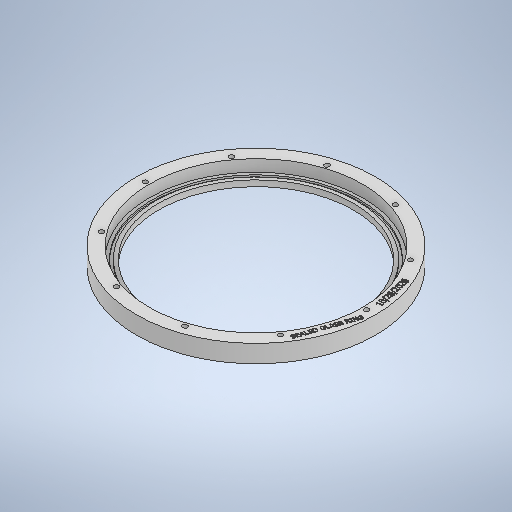
# Autodesk Inventor part: SealedGlassRing_Lowered
Saved by Autodesk Inventor 2025 (Build 290162000, 162)
## iProperties
Created: 2026-10-28
Part Number: SealedGlassRing_Lowered
Material: Generic
Document SubType Name: Modeling
Designer: madhami
Density: 1 g/cm^3
Appearance: Default
Author: madhami
Autodesk Inventor part; units mm, degrees
ref_plane "YZ Plane" through (0, 0, 0) normal (1, 0, 0) x (0, 1, 0)
ref_plane "XZ Plane" through (0, 0, 0) normal (0, 1, 0) x (-1, 0, 0)
ref_plane "XY Plane" through (0, 0, 0) normal (0, 0, 1) x (1, 0, 0)
sketch "Sketch1" plane through (0, 0, 0) normal (1, 0, 0) x (0, 1, 0)
  line L0 (33.6846, 0) -> (-3.2071, 0)
  line L1 (6.7, -110) -> (0, -110)
  line L2 (0, -114) -> (2.5, -114)
  line L3 (2.5, -114) -> (2.5, -117)
  line L4 (2.5, -117) -> (0, -117)
  line L5 (0, -117) -> (0, -135)
  line L6 (0, -135) -> (20, -135)
  line L7 (20, -135) -> (20, -120.5)
  line L8 (20, -120.5) -> (6.7, -120.5)
  line L9 (6.7, -120.5) -> (6.7, -117)
  line L10 (6.7, -117) -> (4.7, -117)
  line L11 (4.7, -117) -> (4.7, -114)
  line L12 (4.7, -114) -> (6.7, -114)
  line L13 (6.7, -114) -> (6.7, -110)
  line L14 (0, -114) -> (0, -110)
  point P0 (0, 0)
  dimension "d0" = 270
  dimension "d1" = 220
  dimension "d2" = 241
  dimension "d4" = 20
  dimension "d5" = 3
  dimension "d6" = 228
  dimension "d7" = 13.3
  dimension "d8" = 2
  dimension "d9" = 2.5
  constraints: 30 end point, 7 perpendicular, 4 point on line, 2 horizontal, 1 parallel, 1 vertical
  measures "d0" diameter of L6 L0
  measures "d1" diameter of L1 L0
  measures "d2" diameter of L8 L0
  measures "d4" distance between parallel lines of L5 L7
  measures "d5" distance of L10.end L11.end
  measures "d6" diameter of L12 L0
  measures "d7" distance between parallel lines of L7 L9
  measures "d8" distance between parallel lines of L9 L11
  measures "d9" distance between parallel lines of L5 L3
revolve "Revolution1" add sketch "Sketch1" angle 360 about axis through (0, 33.6846, 0) along (0, -1, 0)
sketch "Sketch2" plane through (0, 20, 0) normal (0, 1, 0) x (1, 0, 0)
  circle A0 centre (0, 0) radius 125
  line L0 (-189, 0) -> (189, 0) projected
  point P0 (-125, 0)
  dimension "d18" = 250
  constraints: 1 coincident, 1 horizontal alignment, 1 point on line, 2 other
hole "Hole1" at (-125, 20, 0) direction (0, -1, 0) diameter 5.5 end through all
pattern_circular "Circular Pattern1" count 10 over 360 about axis through (0, -10, 0) along (0, 1, 0) of "Hole1"
sketch "Sketch3" plane through (0, 20, 0) normal (0, 1, 0) x (1, 0, 0)
  line L0 (106.4888, -68.4672) -> (128.0893, -6.4393) construction
  line L1 (128.0893, -6.4393) -> (133.5161, -8.3291) construction
  line L2 (133.5161, -8.3291) -> (111.9157, -70.357) construction
  line L3 (111.9157, -70.357) -> (106.4888, -68.4672) construction
  line L4 (123.8949, 10.0524) -> (114.5166, 51.3311) construction
  line L5 (114.5166, 51.3311) -> (121.899, 53.0083) construction
  line L6 (121.899, 53.0083) -> (131.2773, 11.7297) construction
  line L7 (131.2773, 11.7297) -> (123.8949, 10.0524) construction
  spline S0 degree 2 poles (112.004, -68.3756) (111.8255, -68.8883) (111.3607, -69.5331) (111.097, -69.7974) knots 0 0 0 1 2 2 2
  line L8 (111.097, -69.7974) -> (110.3088, -69.5229)
  line L9 (110.3088, -69.5229) -> (110.3248, -69.4769)
  spline S1 degree 2 poles (110.3248, -69.4769) (110.7235, -69.2683) (111.3181, -68.5958) (111.4447, -68.2323) knots 0 0 0 1 2 2 2
  spline S2 degree 2 poles (111.4447, -68.2323) (111.6259, -67.7119) (111.3787, -67.0294) (111.0229, -66.9055) knots 0 0 0 1 2 2 2
  spline S3 degree 2 poles (111.0229, -66.9055) (110.7397, -66.8069) (110.2904, -66.9636) (110.0971, -67.2353) knots 0 0 0 1 2 2 2
  spline S4 degree 2 poles (110.0971, -67.2353) (109.9599, -67.432) (109.7492, -67.7662) (109.5857, -68.0139) knots 0 0 0 1 2 2 2
  spline S5 degree 2 poles (109.5857, -68.0139) (109.4354, -68.2362) (109.1056, -68.5547) (108.8968, -68.6493) knots 0 0 0 1 2 2 2
  spline S6 degree 2 poles (108.8968, -68.6493) (108.6892, -68.7401) (108.2124, -68.7542) (107.9369, -68.6583) knots 0 0 0 1 2 2 2
  spline S7 degree 2 poles (107.9369, -68.6583) (107.3629, -68.4584) (106.8979, -67.2925) (107.1391, -66.5999) knots 0 0 0 1 2 2 2
  spline S8 degree 2 poles (107.1391, -66.5999) (107.2777, -66.2019) (107.6798, -65.5525) (107.9343, -65.3022) knots 0 0 0 1 2 2 2
  line L10 (107.9343, -65.3022) -> (108.6842, -65.5634)
  line L11 (108.6842, -65.5634) -> (108.6683, -65.6093)
  spline S9 degree 2 poles (108.6683, -65.6093) (108.383, -65.7631) (107.8317, -66.3605) (107.6971, -66.747) knots 0 0 0 1 2 2 2
  spline S10 degree 2 poles (107.6971, -66.747) (107.5452, -67.1832) (107.7668, -67.8654) (108.0997, -67.9813) knots 0 0 0 1 2 2 2
  spline S11 degree 2 poles (108.0997, -67.9813) (108.3981, -68.0852) (108.8646, -67.8915) (109.0489, -67.6211) knots 0 0 0 1 2 2 2
  spline S12 degree 2 poles (109.0489, -67.6211) (109.1717, -67.4407) (109.5107, -66.9109) (109.6347, -66.7396) knots 0 0 0 1 2 2 2
  spline S13 degree 2 poles (109.6347, -66.7396) (109.9532, -66.3056) (110.7112, -66.0633) (111.1512, -66.2165) knots 0 0 0 1 2 2 2
  spline S14 degree 2 poles (111.1512, -66.2165) (111.4306, -66.3138) (111.8877, -66.7261) (112.0045, -66.9942) knots 0 0 0 1 2 2 2
  spline S15 degree 2 poles (112.0045, -66.9942) (112.1325, -67.2919) (112.1546, -67.9432) (112.004, -68.3756) knots 0 0 0 1 2 2 2
  line L12 (112.7207, -66.0465) -> (107.9988, -64.4022)
  line L13 (107.9988, -64.4022) -> (109.0275, -61.4481)
  line L14 (109.0275, -61.4481) -> (109.5862, -61.6427)
  line L15 (109.5862, -61.6427) -> (108.776, -63.9692)
  line L16 (108.776, -63.9692) -> (110.0694, -64.4196)
  line L17 (110.0694, -64.4196) -> (110.8249, -62.25)
  line L18 (110.8249, -62.25) -> (111.3836, -62.4445)
  line L19 (111.3836, -62.4445) -> (110.628, -64.6141)
  line L20 (110.628, -64.6141) -> (112.3806, -65.2244)
  line L21 (112.3806, -65.2244) -> (113.1907, -62.8979)
  line L22 (113.1907, -62.8979) -> (113.7494, -63.0925)
  line L23 (113.7494, -63.0925) -> (112.7207, -66.0465)
  line L24 (113.812, -62.9126) -> (109.6445, -59.6765)
  line L25 (109.6445, -59.6765) -> (109.9136, -58.9035)
  line L26 (109.9136, -58.9035) -> (115.1899, -58.9561)
  line L27 (115.1899, -58.9561) -> (114.9593, -59.618)
  line L28 (114.9593, -59.618) -> (113.49, -59.5869)
  line L29 (113.49, -59.5869) -> (112.8623, -61.3892)
  line L30 (112.8623, -61.3892) -> (114.0332, -62.2774)
  line L31 (114.0332, -62.2774) -> (113.812, -62.9126)
  line L32 (112.8943, -59.5725) -> (110.4166, -59.5292)
  line L33 (110.4166, -59.5292) -> (112.3866, -61.0304)
  line L34 (112.3866, -61.0304) -> (112.8943, -59.5725)
  line L35 (116.2985, -55.7724) -> (115.3458, -58.5084)
  line L36 (115.3458, -58.5084) -> (110.6239, -56.864)
  line L37 (110.6239, -56.864) -> (110.8424, -56.2365)
  line L38 (110.8424, -56.2365) -> (115.0056, -57.6863)
  line L39 (115.0056, -57.6863) -> (115.7399, -55.5779)
  line L40 (115.7399, -55.5779) -> (116.2985, -55.7724)
  line L41 (116.4704, -55.2788) -> (111.7485, -53.6345)
  line L42 (111.7485, -53.6345) -> (112.7772, -50.6804)
  line L43 (112.7772, -50.6804) -> (113.3359, -50.875)
  line L44 (113.3359, -50.875) -> (112.5257, -53.2015)
  line L45 (112.5257, -53.2015) -> (113.8191, -53.6519)
  line L46 (113.8191, -53.6519) -> (114.5746, -51.4822)
  line L47 (114.5746, -51.4822) -> (115.1333, -51.6768)
  line L48 (115.1333, -51.6768) -> (114.3778, -53.8464)
  line L49 (114.3778, -53.8464) -> (116.1303, -54.4567)
  line L50 (116.1303, -54.4567) -> (116.9405, -52.1302)
  line L51 (116.9405, -52.1302) -> (117.4991, -52.3248)
  line L52 (117.4991, -52.3248) -> (116.4704, -55.2788)
  spline S16 degree 2 poles (116.6784, -47.092) (117.3251, -47.3172) (118.1833, -48.2039) (118.3209, -48.7452) knots 0 0 0 1 2 2 2
  spline S17 degree 2 poles (118.3209, -48.7452) (118.4214, -49.1835) (118.3173, -49.9753) (118.1174, -50.5493) knots 0 0 0 1 2 2 2
  line L53 (118.1174, -50.5493) -> (117.739, -51.636)
  line L54 (117.739, -51.636) -> (113.0171, -49.9917)
  line L55 (113.0171, -49.9917) -> (113.3915, -48.9164)
  spline S18 degree 2 poles (113.3915, -48.9164) (113.6234, -48.2506) (114.0862, -47.5623) (114.3555, -47.3557) knots 0 0 0 1 2 2 2
  spline S19 degree 2 poles (114.3555, -47.3557) (114.8164, -47.0056) (115.9896, -46.8521) (116.6784, -47.092) knots 0 0 0 1 2 2 2
  spline S20 degree 2 poles (116.4429, -47.7436) (115.8995, -47.5544) (115.0052, -47.6463) (114.6631, -47.9262) knots 0 0 0 1 2 2 2
  spline S21 degree 2 poles (114.6631, -47.9262) (114.4259, -48.1268) (114.0935, -48.6503) (113.9456, -49.075) knots 0 0 0 1 2 2 2
  line L56 (113.9456, -49.075) -> (113.779, -49.5533)
  line L57 (113.779, -49.5533) -> (117.4141, -50.8192)
  line L58 (117.4141, -50.8192) -> (117.5807, -50.3409)
  spline S22 degree 2 poles (117.5807, -50.3409) (117.726, -49.9238) (117.8119, -49.2458) (117.7213, -48.9268) knots 0 0 0 1 2 2 2
  spline S23 degree 2 poles (117.7213, -48.9268) (117.614, -48.5205) (116.9939, -47.9355) (116.4429, -47.7436) knots 0 0 0 1 2 2 2
  spline S24 degree 2 poles (120.7597, -43.2574) (120.5851, -43.7586) (119.9899, -44.4824) (119.576, -44.6729) knots 0 0 0 1 2 2 2
  spline S25 degree 2 poles (119.576, -44.6729) (119.1583, -44.8621) (118.1217, -44.8572) (117.5209, -44.648) knots 0 0 0 1 2 2 2
  spline S26 degree 2 poles (117.5209, -44.648) (116.9508, -44.4495) (116.1596, -43.8136) (115.9422, -43.4032) knots 0 0 0 1 2 2 2
  spline S27 degree 2 poles (115.9422, -43.4032) (115.7321, -43.0083) (115.6886, -42.0492) (115.8631, -41.5479) knots 0 0 0 1 2 2 2
  spline S28 degree 2 poles (115.8631, -41.5479) (115.9471, -41.3068) (116.1679, -40.8946) (116.2984, -40.7169) knots 0 0 0 1 2 2 2
  spline S29 degree 2 poles (116.2984, -40.7169) (116.4003, -40.5722) (116.7045, -40.2405) (116.8071, -40.1432) knots 0 0 0 1 2 2 2
  line L59 (116.8071, -40.1432) -> (117.5647, -40.4071)
  line L60 (117.5647, -40.4071) -> (117.5461, -40.4607)
  spline S30 degree 2 poles (117.5461, -40.4607) (117.4014, -40.5433) (117.1273, -40.7267) (116.9402, -40.919) knots 0 0 0 1 2 2 2
  spline S31 degree 2 poles (116.9402, -40.919) (116.7779, -41.077) (116.4798, -41.5267) (116.3812, -41.8098) knots 0 0 0 1 2 2 2
  spline S32 degree 2 poles (116.3812, -41.8098) (116.144, -42.4909) (116.8763, -43.6899) (117.7296, -43.987) knots 0 0 0 1 2 2 2
  spline S33 degree 2 poles (117.7296, -43.987) (118.2041, -44.1523) (118.9931, -44.1782) (119.3113, -44.053) knots 0 0 0 1 2 2 2
  spline S34 degree 2 poles (119.3113, -44.053) (119.6268, -43.9355) (120.0831, -43.4508) (120.2083, -43.0911) knots 0 0 0 1 2 2 2
  spline S35 degree 2 poles (120.2083, -43.0911) (120.3003, -42.8271) (120.4076, -42.2724) (120.3937, -42.0659) knots 0 0 0 1 2 2 2
  line L61 (120.3937, -42.0659) -> (119.1731, -41.6408)
  line L62 (119.1731, -41.6408) -> (118.792, -42.7352)
  line L63 (118.792, -42.7352) -> (118.241, -42.5433)
  line L64 (118.241, -42.5433) -> (118.8379, -40.829)
  line L65 (118.8379, -40.829) -> (120.9004, -41.5472)
  spline S36 degree 2 poles (120.9004, -41.5472) (120.9127, -41.6845) (120.936, -42.1474) (120.9258, -42.3369) knots 0 0 0 1 2 2 2
  spline S37 degree 2 poles (120.9258, -42.3369) (120.9134, -42.5943) (120.8516, -42.9933) (120.7597, -43.2574) knots 0 0 0 1 2 2 2
  line L66 (122.4414, -38.1323) -> (121.4887, -40.8683)
  line L67 (121.4887, -40.8683) -> (116.7668, -39.2239)
  line L68 (116.7668, -39.2239) -> (116.9853, -38.5964)
  line L69 (116.9853, -38.5964) -> (121.1486, -40.0462)
  line L70 (121.1486, -40.0462) -> (121.8828, -37.9378)
  line L71 (121.8828, -37.9378) -> (122.4414, -38.1323)
  line L72 (122.4361, -38.1476) -> (118.2686, -34.9115)
  line L73 (118.2686, -34.9115) -> (118.5377, -34.1385)
  line L74 (118.5377, -34.1385) -> (123.8139, -34.191)
  line L75 (123.8139, -34.191) -> (123.5834, -34.853)
  line L76 (123.5834, -34.853) -> (122.114, -34.8219)
  line L77 (122.114, -34.8219) -> (121.4864, -36.6241)
  line L78 (121.4864, -36.6241) -> (122.6573, -37.5124)
  line L79 (122.6573, -37.5124) -> (122.4361, -38.1476)
  line L80 (121.5184, -34.8075) -> (119.0407, -34.7642)
  line L81 (119.0407, -34.7642) -> (121.0107, -36.2654)
  line L82 (121.0107, -36.2654) -> (121.5184, -34.8075)
  spline S38 degree 2 poles (124.5124, -32.4564) (124.3339, -32.9691) (123.8691, -33.6139) (123.6054, -33.8782) knots 0 0 0 1 2 2 2
  line L83 (123.6054, -33.8782) -> (122.8172, -33.6037)
  line L84 (122.8172, -33.6037) -> (122.8331, -33.5577)
  spline S39 degree 2 poles (122.8331, -33.5577) (123.2319, -33.3491) (123.8265, -32.6766) (123.9531, -32.3131) knots 0 0 0 1 2 2 2
  spline S40 degree 2 poles (123.9531, -32.3131) (124.1343, -31.7926) (123.8871, -31.1102) (123.5313, -30.9863) knots 0 0 0 1 2 2 2
  spline S41 degree 2 poles (123.5313, -30.9863) (123.2481, -30.8877) (122.7988, -31.0444) (122.6055, -31.316) knots 0 0 0 1 2 2 2
  spline S42 degree 2 poles (122.6055, -31.316) (122.4683, -31.5128) (122.2576, -31.847) (122.0941, -32.0947) knots 0 0 0 1 2 2 2
  spline S43 degree 2 poles (122.0941, -32.0947) (121.9437, -32.317) (121.614, -32.6355) (121.4052, -32.7301) knots 0 0 0 1 2 2 2
  spline S44 degree 2 poles (121.4052, -32.7301) (121.1976, -32.8209) (120.7208, -32.835) (120.4452, -32.7391) knots 0 0 0 1 2 2 2
  spline S45 degree 2 poles (120.4452, -32.7391) (119.8713, -32.5392) (119.4063, -31.3733) (119.6475, -30.6807) knots 0 0 0 1 2 2 2
  spline S46 degree 2 poles (119.6475, -30.6807) (119.7861, -30.2827) (120.1881, -29.6333) (120.4426, -29.383) knots 0 0 0 1 2 2 2
  line L85 (120.4426, -29.383) -> (121.1926, -29.6441)
  line L86 (121.1926, -29.6441) -> (121.1766, -29.6901)
  spline S47 degree 2 poles (121.1766, -29.6901) (120.8914, -29.8439) (120.3401, -30.4413) (120.2055, -30.8278) knots 0 0 0 1 2 2 2
  spline S48 degree 2 poles (120.2055, -30.8278) (120.0536, -31.264) (120.2752, -31.9461) (120.6081, -32.0621) knots 0 0 0 1 2 2 2
  spline S49 degree 2 poles (120.6081, -32.0621) (120.9065, -32.166) (121.373, -31.9723) (121.5573, -31.7019) knots 0 0 0 1 2 2 2
  spline S50 degree 2 poles (121.5573, -31.7019) (121.6801, -31.5215) (122.0191, -30.9917) (122.1431, -30.8204) knots 0 0 0 1 2 2 2
  spline S51 degree 2 poles (122.1431, -30.8204) (122.4616, -30.3864) (123.2196, -30.1441) (123.6596, -30.2973) knots 0 0 0 1 2 2 2
  spline S52 degree 2 poles (123.6596, -30.2973) (123.939, -30.3946) (124.3961, -30.8069) (124.5129, -31.075) knots 0 0 0 1 2 2 2
  spline S53 degree 2 poles (124.5129, -31.075) (124.6409, -31.3727) (124.663, -32.024) (124.5124, -32.4564) knots 0 0 0 1 2 2 2
  spline S54 degree 2 poles (125.7717, -28.8403) (125.5931, -29.3531) (125.1283, -29.9978) (124.8646, -30.2621) knots 0 0 0 1 2 2 2
  line L87 (124.8646, -30.2621) -> (124.0764, -29.9876)
  line L88 (124.0764, -29.9876) -> (124.0924, -29.9417)
  spline S55 degree 2 poles (124.0924, -29.9417) (124.4911, -29.733) (125.0857, -29.0605) (125.2123, -28.697) knots 0 0 0 1 2 2 2
  spline S56 degree 2 poles (125.2123, -28.697) (125.3935, -28.1766) (125.1464, -27.4942) (124.7905, -27.3702) knots 0 0 0 1 2 2 2
  spline S57 degree 2 poles (124.7905, -27.3702) (124.5073, -27.2716) (124.058, -27.4284) (123.8647, -27.7) knots 0 0 0 1 2 2 2
  spline S58 degree 2 poles (123.8647, -27.7) (123.7276, -27.8968) (123.5168, -28.231) (123.3533, -28.4787) knots 0 0 0 1 2 2 2
  spline S59 degree 2 poles (123.3533, -28.4787) (123.203, -28.7009) (122.8732, -29.0195) (122.6644, -29.1141) knots 0 0 0 1 2 2 2
  spline S60 degree 2 poles (122.6644, -29.1141) (122.4569, -29.2048) (121.98, -29.219) (121.7045, -29.123) knots 0 0 0 1 2 2 2
  spline S61 degree 2 poles (121.7045, -29.123) (121.1305, -28.9231) (120.6655, -27.7573) (120.9067, -27.0647) knots 0 0 0 1 2 2 2
  spline S62 degree 2 poles (120.9067, -27.0647) (121.0453, -26.6667) (121.4474, -26.0173) (121.7019, -25.7669) knots 0 0 0 1 2 2 2
  line L89 (121.7019, -25.7669) -> (122.4519, -26.0281)
  line L90 (122.4519, -26.0281) -> (122.4359, -26.074)
  spline S63 degree 2 poles (122.4359, -26.074) (122.1506, -26.2278) (121.5993, -26.8253) (121.4647, -27.2118) knots 0 0 0 1 2 2 2
  spline S64 degree 2 poles (121.4647, -27.2118) (121.3128, -27.648) (121.5344, -28.3301) (121.8673, -28.446) knots 0 0 0 1 2 2 2
  spline S65 degree 2 poles (121.8673, -28.446) (122.1658, -28.55) (122.6322, -28.3563) (122.8165, -28.0858) knots 0 0 0 1 2 2 2
  spline S66 degree 2 poles (122.8165, -28.0858) (122.9394, -27.9055) (123.2783, -27.3757) (123.4024, -27.2043) knots 0 0 0 1 2 2 2
  spline S67 degree 2 poles (123.4024, -27.2043) (123.7208, -26.7703) (124.4788, -26.528) (124.9189, -26.6813) knots 0 0 0 1 2 2 2
  spline S68 degree 2 poles (124.9189, -26.6813) (125.1982, -26.7785) (125.6553, -27.1909) (125.7722, -27.459) knots 0 0 0 1 2 2 2
  spline S69 degree 2 poles (125.7722, -27.459) (125.9002, -27.7567) (125.9222, -28.4079) (125.7717, -28.8403) knots 0 0 0 1 2 2 2
  line L91 (128.4671, -20.829) -> (128.1833, -21.644)
  line L92 (128.1833, -21.644) -> (125.7848, -22.4821)
  line L93 (125.7848, -22.4821) -> (125.5343, -23.2014)
  line L94 (125.5343, -23.2014) -> (127.4131, -23.8557)
  line L95 (127.4131, -23.8557) -> (127.1946, -24.4833)
  line L96 (127.1946, -24.4833) -> (122.4727, -22.8389)
  line L97 (122.4727, -22.8389) -> (122.8964, -21.6221)
  spline S70 degree 2 poles (122.8964, -21.6221) (123.0377, -21.2165) (123.3162, -20.7) (123.5636, -20.5072) knots 0 0 0 1 2 2 2
  spline S71 degree 2 poles (123.5636, -20.5072) (123.8109, -20.3144) (124.4121, -20.202) (124.7833, -20.3313) knots 0 0 0 1 2 2 2
  spline S72 degree 2 poles (124.7833, -20.3313) (125.2998, -20.5112) (125.8162, -21.2831) (125.8273, -21.7932) knots 0 0 0 1 2 2 2
  line L98 (125.8273, -21.7932) -> (128.4671, -20.829)
  spline S73 degree 2 poles (124.6051, -21.0029) (124.3985, -20.931) (124.0303, -20.9658) (123.8737, -21.0829) knots 0 0 0 1 2 2 2
  spline S74 degree 2 poles (123.8737, -21.0829) (123.739, -21.1861) (123.5424, -21.5167) (123.4518, -21.7769) knots 0 0 0 1 2 2 2
  line L99 (123.4518, -21.7769) -> (123.2346, -22.4006)
  line L100 (123.2346, -22.4006) -> (125.0101, -23.0189)
  line L101 (125.0101, -23.0189) -> (125.2019, -22.4679)
  spline S75 degree 2 poles (125.2019, -22.4679) (125.2966, -22.1962) (125.3515, -21.7305) (125.2542, -21.5293) knots 0 0 0 1 2 2 2
  spline S76 degree 2 poles (125.2542, -21.5293) (125.1721, -21.3462) (124.85, -21.0882) (124.6051, -21.0029) knots 0 0 0 1 2 2 2
  line L102 (129.1707, -18.8086) -> (128.5337, -20.6376)
  line L103 (128.5337, -20.6376) -> (128.0516, -20.4697)
  line L104 (128.0516, -20.4697) -> (128.2608, -19.869)
  line L105 (128.2608, -19.869) -> (124.5032, -18.5604)
  line L106 (124.5032, -18.5604) -> (124.294, -19.1612)
  line L107 (124.294, -19.1612) -> (123.8119, -18.9933)
  line L108 (123.8119, -18.9933) -> (124.4488, -17.1642)
  line L109 (124.4488, -17.1642) -> (124.9309, -17.3321)
  line L110 (124.9309, -17.3321) -> (124.7217, -17.9329)
  line L111 (124.7217, -17.9329) -> (128.4793, -19.2414)
  line L112 (128.4793, -19.2414) -> (128.6886, -18.6407)
  line L113 (128.6886, -18.6407) -> (129.1707, -18.8086)
  line L114 (130.6178, -14.653) -> (130.3726, -15.3571)
  line L115 (130.3726, -15.3571) -> (125.5737, -16.0285)
  line L116 (125.5737, -16.0285) -> (129.6451, -17.4463)
  line L117 (129.6451, -17.4463) -> (129.4412, -18.0318)
  line L118 (129.4412, -18.0318) -> (124.7193, -16.3875)
  line L119 (124.7193, -16.3875) -> (125.0298, -15.4959)
  line L120 (125.0298, -15.4959) -> (129.4305, -14.896)
  line L121 (129.4305, -14.896) -> (125.6921, -13.5941)
  line L122 (125.6921, -13.5941) -> (125.8959, -13.0087)
  line L123 (125.8959, -13.0087) -> (130.6178, -14.653)
  spline S77 degree 2 poles (131.7317, -11.7501) (131.5571, -12.2514) (130.9619, -12.9751) (130.548, -13.1656) knots 0 0 0 1 2 2 2
  spline S78 degree 2 poles (130.548, -13.1656) (130.1303, -13.3548) (129.0937, -13.35) (128.4929, -13.1407) knots 0 0 0 1 2 2 2
  spline S79 degree 2 poles (128.4929, -13.1407) (127.9228, -12.9422) (127.1316, -12.3063) (126.9141, -11.8959) knots 0 0 0 1 2 2 2
  spline S80 degree 2 poles (126.9141, -11.8959) (126.7041, -11.501) (126.6606, -10.5419) (126.8351, -10.0406) knots 0 0 0 1 2 2 2
  spline S81 degree 2 poles (126.8351, -10.0406) (126.9191, -9.7996) (127.1399, -9.3873) (127.2704, -9.2097) knots 0 0 0 1 2 2 2
  spline S82 degree 2 poles (127.2704, -9.2097) (127.3723, -9.0649) (127.6765, -8.7333) (127.7791, -8.636) knots 0 0 0 1 2 2 2
  line L124 (127.7791, -8.636) -> (128.5367, -8.8998)
  line L125 (128.5367, -8.8998) -> (128.5181, -8.9534)
  spline S83 degree 2 poles (128.5181, -8.9534) (128.3734, -9.036) (128.0993, -9.2195) (127.9122, -9.4117) knots 0 0 0 1 2 2 2
  spline S84 degree 2 poles (127.9122, -9.4117) (127.7499, -9.5697) (127.4518, -10.0194) (127.3532, -10.3025) knots 0 0 0 1 2 2 2
  spline S85 degree 2 poles (127.3532, -10.3025) (127.116, -10.9837) (127.8483, -12.1826) (128.7016, -12.4798) knots 0 0 0 1 2 2 2
  spline S86 degree 2 poles (128.7016, -12.4798) (129.1761, -12.645) (129.9651, -12.6709) (130.2833, -12.5457) knots 0 0 0 1 2 2 2
  spline S87 degree 2 poles (130.2833, -12.5457) (130.5988, -12.4282) (131.0551, -11.9435) (131.1803, -11.5838) knots 0 0 0 1 2 2 2
  spline S88 degree 2 poles (131.1803, -11.5838) (131.2723, -11.3198) (131.3796, -10.7651) (131.3657, -10.5586) knots 0 0 0 1 2 2 2
  line L126 (131.3657, -10.5586) -> (130.1451, -10.1335)
  line L127 (130.1451, -10.1335) -> (129.764, -11.2279)
  line L128 (129.764, -11.2279) -> (129.213, -11.036)
  line L129 (129.213, -11.036) -> (129.8099, -9.3217)
  line L130 (129.8099, -9.3217) -> (131.8724, -10.04)
  spline S89 degree 2 poles (131.8724, -10.04) (131.8847, -10.1773) (131.908, -10.6402) (131.8978, -10.8297) knots 0 0 0 1 2 2 2
  spline S90 degree 2 poles (131.8978, -10.8297) (131.8853, -11.0871) (131.8236, -11.4861) (131.7317, -11.7501) knots 0 0 0 1 2 2 2
  line L131 (129.1567, 15.1819) -> (129.8051, 12.3276)
  line L132 (129.8051, 12.3276) -> (129.2077, 12.1919)
  line L133 (129.2077, 12.1919) -> (128.9664, 13.2539)
  line L134 (128.9664, 13.2539) -> (125.0453, 12.3631)
  line L135 (125.0453, 12.3631) -> (125.2866, 11.301)
  line L136 (125.2866, 11.301) -> (124.7508, 11.1793)
  spline S91 degree 2 poles (124.7508, 11.1793) (124.614, 11.7814) (124.1434, 12.2729) (123.6606, 12.2031) knots 0 0 0 1 2 2 2
  line L137 (123.6606, 12.2031) -> (123.5227, 12.81)
  line L138 (123.5227, 12.81) -> (128.7952, 14.0078)
  line L139 (128.7952, 14.0078) -> (128.5592, 15.0462)
  line L140 (128.5592, 15.0462) -> (129.1567, 15.1819)
  spline S92 degree 2 poles (125.1594, 19.235) (126.7335, 19.5926) (128.416, 19.0125) (128.6325, 18.0595) knots 0 0 0 1 2 2 2
  spline S93 degree 2 poles (128.6325, 18.0595) (128.8523, 17.0923) (127.555, 15.8452) (126.014, 15.4951) knots 0 0 0 1 2 2 2
  spline S94 degree 2 poles (126.014, 15.4951) (124.4304, 15.1353) (122.7574, 15.7175) (122.5398, 16.6753) knots 0 0 0 1 2 2 2
  spline S95 degree 2 poles (122.5398, 16.6753) (122.3211, 17.6378) (123.6326, 18.8881) (125.1594, 19.235) knots 0 0 0 1 2 2 2
  spline S96 degree 2 poles (127.1705, 18.6348) (126.8554, 18.6829) (125.9425, 18.5752) (125.3403, 18.4384) knots 0 0 0 1 2 2 2
  spline S97 degree 2 poles (125.3403, 18.4384) (124.7382, 18.3016) (123.8731, 18.0054) (123.6013, 17.819) knots 0 0 0 1 2 2 2
  spline S98 degree 2 poles (123.6013, 17.819) (123.3295, 17.6326) (123.1151, 17.15) (123.1894, 16.8229) knots 0 0 0 1 2 2 2
  spline S99 degree 2 poles (123.1894, 16.8229) (123.2637, 16.4957) (123.6678, 16.1438) (124.004, 16.0905) knots 0 0 0 1 2 2 2
  spline S100 degree 2 poles (124.004, 16.0905) (124.3296, 16.0398) (125.2594, 16.1613) (125.8331, 16.2916) knots 0 0 0 1 2 2 2
  spline S101 degree 2 poles (125.8331, 16.2916) (126.4495, 16.4317) (127.2572, 16.695) (127.5516, 16.8915) knots 0 0 0 1 2 2 2
  spline S102 degree 2 poles (127.5516, 16.8915) (127.8292, 17.0742) (128.0605, 17.5706) (127.983, 17.9119) knots 0 0 0 1 2 2 2
  spline S103 degree 2 poles (127.983, 17.9119) (127.9097, 18.2344) (127.5056, 18.5863) (127.1705, 18.6348) knots 0 0 0 1 2 2 2
  line L141 (121.2503, 21.6926) -> (129.153, 21.0797)
  line L142 (129.153, 21.0797) -> (129.3038, 20.4159)
  line L143 (129.3038, 20.4159) -> (121.4033, 21.0193)
  line L144 (121.4033, 21.0193) -> (121.2503, 21.6926)
  line L145 (126.3957, 27.3342) -> (127.2155, 23.7259)
  line L146 (127.2155, 23.7259) -> (126.3858, 23.5374)
  spline S104 degree 2 poles (126.3858, 23.5374) (125.9323, 23.8433) (125.097, 24.3815) (124.6566, 24.6304) knots 0 0 0 1 2 2 2
  spline S105 degree 2 poles (124.6566, 24.6304) (123.7697, 25.132) (122.7769, 25.42) (122.3075, 25.3134) knots 0 0 0 1 2 2 2
  spline S106 degree 2 poles (122.3075, 25.3134) (122.0609, 25.2573) (121.7256, 25.0216) (121.6383, 24.8572) knots 0 0 0 1 2 2 2
  spline S107 degree 2 poles (121.6383, 24.8572) (121.551, 24.6927) (121.5143, 24.3055) (121.5639, 24.0874) knots 0 0 0 1 2 2 2
  spline S108 degree 2 poles (121.5639, 24.0874) (121.6113, 23.8787) (121.8125, 23.4757) (121.9373, 23.2996) knots 0 0 0 1 2 2 2
  spline S109 degree 2 poles (121.9373, 23.2996) (122.0414, 23.1488) (122.3011, 22.8836) (122.389, 22.8039) knots 0 0 0 1 2 2 2
  line L147 (122.389, 22.8039) -> (122.3987, 22.7612)
  line L148 (122.3987, 22.7612) -> (121.5642, 22.5716)
  spline S110 degree 2 poles (121.5642, 22.5716) (121.3907, 22.7865) (120.9613, 23.6014) (120.8729, 23.9902) knots 0 0 0 1 2 2 2
  spline S111 degree 2 poles (120.8729, 23.9902) (120.6866, 24.8105) (121.3442, 25.9322) (122.0838, 26.1002) knots 0 0 0 1 2 2 2
  spline S112 degree 2 poles (122.0838, 26.1002) (122.43, 26.1789) (123.045, 26.1491) (123.3239, 26.0628) knots 0 0 0 1 2 2 2
  spline S113 degree 2 poles (123.3239, 26.0628) (123.6123, 25.9788) (124.2086, 25.6805) (124.5021, 25.5078) knots 0 0 0 1 2 2 2
  spline S114 degree 2 poles (124.5021, 25.5078) (124.9891, 25.2295) (126.0578, 24.52) (126.3705, 24.3068) knots 0 0 0 1 2 2 2
  line L149 (126.3705, 24.3068) -> (125.7177, 27.1801)
  line L150 (125.7177, 27.1801) -> (126.3957, 27.3342)
  spline S115 degree 2 poles (125.949, 29.9152) (126.0481, 29.479) (125.9499, 28.7038) (125.7652, 28.3976) knots 0 0 0 1 2 2 2
  spline S116 degree 2 poles (125.7652, 28.3976) (125.5842, 28.0971) (124.9975, 27.6946) (124.6324, 27.6117) knots 0 0 0 1 2 2 2
  spline S117 degree 2 poles (124.6324, 27.6117) (124.1583, 27.5039) (123.2465, 27.8303) (122.8995, 28.2601) knots 0 0 0 1 2 2 2
  line L151 (122.8995, 28.2601) -> (122.8758, 28.2547)
  spline S118 degree 2 poles (122.8758, 28.2547) (122.7225, 27.7661) (122.2199, 27.2131) (121.7742, 27.1119) knots 0 0 0 1 2 2 2
  spline S119 degree 2 poles (121.7742, 27.1119) (121.1152, 26.9621) (120.0071, 27.7575) (119.8325, 28.5256) knots 0 0 0 1 2 2 2
  spline S120 degree 2 poles (119.8325, 28.5256) (119.6516, 29.3221) (120.2674, 30.4742) (120.9217, 30.6229) knots 0 0 0 1 2 2 2
  spline S121 degree 2 poles (120.9217, 30.6229) (121.3152, 30.7123) (122.1878, 30.4269) (122.504, 30.045) knots 0 0 0 1 2 2 2
  line L152 (122.504, 30.045) -> (122.5277, 30.0504)
  spline S122 degree 2 poles (122.5277, 30.0504) (122.6484, 30.6163) (123.2116, 31.2977) (123.7521, 31.4205) knots 0 0 0 1 2 2 2
  spline S123 degree 2 poles (123.7521, 31.4205) (124.5013, 31.5907) (125.7637, 30.7307) (125.949, 29.9152) knots 0 0 0 1 2 2 2
  spline S124 degree 2 poles (124.0111, 30.6317) (123.6508, 30.5498) (123.2887, 30.1684) (123.1621, 29.7158) knots 0 0 0 1 2 2 2
  spline S125 degree 2 poles (123.1621, 29.7158) (123.1164, 29.5658) (123.0422, 29.0803) (122.992, 28.7747) knots 0 0 0 1 2 2 2
  spline S126 degree 2 poles (122.992, 28.7747) (123.2786, 28.5008) (123.9926, 28.299) (124.3956, 28.3905) knots 0 0 0 1 2 2 2
  spline S127 degree 2 poles (124.3956, 28.3905) (124.9267, 28.5112) (125.4735, 29.3086) (125.3636, 29.7922) knots 0 0 0 1 2 2 2
  spline S128 degree 2 poles (125.3636, 29.7922) (125.2516, 30.2853) (124.5232, 30.7481) (124.0111, 30.6317) knots 0 0 0 1 2 2 2
  spline S129 degree 2 poles (121.1057, 29.8569) (120.7121, 29.7675) (120.3054, 29.1217) (120.4121, 28.6523) knots 0 0 0 1 2 2 2
  spline S130 degree 2 poles (120.4121, 28.6523) (120.509, 28.2255) (121.1023, 27.7869) (121.5053, 27.8785) knots 0 0 0 1 2 2 2
  spline S131 degree 2 poles (121.5053, 27.8785) (121.7945, 27.9442) (122.134, 28.3155) (122.2317, 28.6319) knots 0 0 0 1 2 2 2
  spline S132 degree 2 poles (122.2317, 28.6319) (122.2711, 28.7655) (122.3893, 29.3209) (122.4093, 29.5398) knots 0 0 0 1 2 2 2
  spline S133 degree 2 poles (122.4093, 29.5398) (122.071, 29.822) (121.4613, 29.9377) (121.1057, 29.8569) knots 0 0 0 1 2 2 2
  line L153 (118.5562, 33.5508) -> (126.4589, 32.938)
  line L154 (126.4589, 32.938) -> (126.6097, 32.2742)
  line L155 (126.6097, 32.2742) -> (118.7092, 32.8776)
  line L156 (118.7092, 32.8776) -> (118.5562, 33.5508)
  line L157 (123.7016, 39.1924) -> (124.5214, 35.5842)
  line L158 (124.5214, 35.5842) -> (123.6916, 35.3957)
  spline S134 degree 2 poles (123.6916, 35.3957) (123.2382, 35.7015) (122.4029, 36.2397) (121.9624, 36.4887) knots 0 0 0 1 2 2 2
  spline S135 degree 2 poles (121.9624, 36.4887) (121.0756, 36.9903) (120.0828, 37.2783) (119.6134, 37.1716) knots 0 0 0 1 2 2 2
  spline S136 degree 2 poles (119.6134, 37.1716) (119.3668, 37.1156) (119.0314, 36.8799) (118.9442, 36.7154) knots 0 0 0 1 2 2 2
  spline S137 degree 2 poles (118.9442, 36.7154) (118.8569, 36.551) (118.8202, 36.1637) (118.8697, 35.9456) knots 0 0 0 1 2 2 2
  spline S138 degree 2 poles (118.8697, 35.9456) (118.9171, 35.737) (119.1184, 35.334) (119.2432, 35.1579) knots 0 0 0 1 2 2 2
  spline S139 degree 2 poles (119.2432, 35.1579) (119.3473, 35.007) (119.6069, 34.7419) (119.6949, 34.6622) knots 0 0 0 1 2 2 2
  line L159 (119.6949, 34.6622) -> (119.7045, 34.6195)
  line L160 (119.7045, 34.6195) -> (118.8701, 34.4299)
  spline S140 degree 2 poles (118.8701, 34.4299) (118.6966, 34.6448) (118.2671, 35.4597) (118.1788, 35.8485) knots 0 0 0 1 2 2 2
  spline S141 degree 2 poles (118.1788, 35.8485) (117.9924, 36.6687) (118.6501, 37.7904) (119.3897, 37.9585) knots 0 0 0 1 2 2 2
  spline S142 degree 2 poles (119.3897, 37.9585) (119.7358, 38.0371) (120.3509, 38.0073) (120.6298, 37.9211) knots 0 0 0 1 2 2 2
  spline S143 degree 2 poles (120.6298, 37.9211) (120.9181, 37.837) (121.5144, 37.5387) (121.808, 37.3661) knots 0 0 0 1 2 2 2
  spline S144 degree 2 poles (121.808, 37.3661) (122.295, 37.0878) (123.3637, 36.3782) (123.6764, 36.1651) knots 0 0 0 1 2 2 2
  line L161 (123.6764, 36.1651) -> (123.0236, 39.0384)
  line L162 (123.0236, 39.0384) -> (123.7016, 39.1924)
  spline S145 degree 2 poles (119.7711, 42.9515) (121.3453, 43.3091) (123.0277, 42.7291) (123.2443, 41.776) knots 0 0 0 1 2 2 2
  spline S146 degree 2 poles (123.2443, 41.776) (123.464, 40.8088) (122.1667, 39.5617) (120.6258, 39.2116) knots 0 0 0 1 2 2 2
  spline S147 degree 2 poles (120.6258, 39.2116) (119.0422, 38.8518) (117.3692, 39.434) (117.1516, 40.3918) knots 0 0 0 1 2 2 2
  spline S148 degree 2 poles (117.1516, 40.3918) (116.9329, 41.3543) (118.2444, 42.6046) (119.7711, 42.9515) knots 0 0 0 1 2 2 2
  spline S149 degree 2 poles (121.7823, 42.3514) (121.4672, 42.3994) (120.5542, 42.2918) (119.9521, 42.1549) knots 0 0 0 1 2 2 2
  spline S150 degree 2 poles (119.9521, 42.1549) (119.3499, 42.0181) (118.4848, 41.7219) (118.2131, 41.5355) knots 0 0 0 1 2 2 2
  spline S151 degree 2 poles (118.2131, 41.5355) (117.9413, 41.3491) (117.7268, 40.8665) (117.8011, 40.5394) knots 0 0 0 1 2 2 2
  spline S152 degree 2 poles (117.8011, 40.5394) (117.8755, 40.2122) (118.2795, 39.8603) (118.6157, 39.807) knots 0 0 0 1 2 2 2
  spline S153 degree 2 poles (118.6157, 39.807) (118.9414, 39.7563) (119.8711, 39.8778) (120.4448, 40.0082) knots 0 0 0 1 2 2 2
  spline S154 degree 2 poles (120.4448, 40.0082) (121.0612, 40.1482) (121.869, 40.4115) (122.1634, 40.608) knots 0 0 0 1 2 2 2
  spline S155 degree 2 poles (122.1634, 40.608) (122.441, 40.7908) (122.6723, 41.2871) (122.5947, 41.6285) knots 0 0 0 1 2 2 2
  spline S156 degree 2 poles (122.5947, 41.6285) (122.5214, 41.9509) (122.1174, 42.3028) (121.7823, 42.3514) knots 0 0 0 1 2 2 2
  line L163 (121.7066, 47.9735) -> (122.5264, 44.3653)
  line L164 (122.5264, 44.3653) -> (121.6966, 44.1768)
  spline S157 degree 2 poles (121.6966, 44.1768) (121.2432, 44.4826) (120.4079, 45.0208) (119.9674, 45.2698) knots 0 0 0 1 2 2 2
  spline S158 degree 2 poles (119.9674, 45.2698) (119.0806, 45.7714) (118.0877, 46.0594) (117.6183, 45.9527) knots 0 0 0 1 2 2 2
  spline S159 degree 2 poles (117.6183, 45.9527) (117.3718, 45.8967) (117.0364, 45.6609) (116.9491, 45.4965) knots 0 0 0 1 2 2 2
  spline S160 degree 2 poles (116.9491, 45.4965) (116.8618, 45.3321) (116.8252, 44.9448) (116.8747, 44.7267) knots 0 0 0 1 2 2 2
  spline S161 degree 2 poles (116.8747, 44.7267) (116.9221, 44.5181) (117.1234, 44.115) (117.2482, 43.939) knots 0 0 0 1 2 2 2
  spline S162 degree 2 poles (117.2482, 43.939) (117.3522, 43.7881) (117.6119, 43.523) (117.6998, 43.4432) knots 0 0 0 1 2 2 2
  line L165 (117.6998, 43.4432) -> (117.7095, 43.4006)
  line L166 (117.7095, 43.4006) -> (116.875, 43.211)
  spline S163 degree 2 poles (116.875, 43.211) (116.7016, 43.4259) (116.2721, 44.2408) (116.1838, 44.6296) knots 0 0 0 1 2 2 2
  spline S164 degree 2 poles (116.1838, 44.6296) (115.9974, 45.4498) (116.655, 46.5715) (117.3947, 46.7396) knots 0 0 0 1 2 2 2
  spline S165 degree 2 poles (117.3947, 46.7396) (117.7408, 46.8182) (118.3559, 46.7884) (118.6348, 46.7022) knots 0 0 0 1 2 2 2
  spline S166 degree 2 poles (118.6348, 46.7022) (118.9231, 46.6181) (119.5194, 46.3198) (119.8129, 46.1472) knots 0 0 0 1 2 2 2
  spline S167 degree 2 poles (119.8129, 46.1472) (120.3, 45.8689) (121.3687, 45.1593) (121.6814, 44.9462) knots 0 0 0 1 2 2 2
  line L167 (121.6814, 44.9462) -> (121.0286, 47.8195)
  line L168 (121.0286, 47.8195) -> (121.7066, 47.9735)
  spline S168 degree 2 poles (118.7921, 52.0232) (119.2425, 52.1256) (120.0737, 52.0003) (120.3869, 51.8072) knots 0 0 0 1 2 2 2
  spline S169 degree 2 poles (120.3869, 51.8072) (120.7164, 51.6078) (121.1448, 51.017) (121.2342, 50.6235) knots 0 0 0 1 2 2 2
  spline S170 degree 2 poles (121.2342, 50.6235) (121.3236, 50.23) (121.2056, 49.5201) (120.9961, 49.2132) knots 0 0 0 1 2 2 2
  spline S171 degree 2 poles (120.9961, 49.2132) (120.7474, 48.8376) (119.7581, 48.2538) (118.9806, 48.0772) knots 0 0 0 1 2 2 2
  spline S172 degree 2 poles (118.9806, 48.0772) (118.2172, 47.9037) (116.9181, 47.9377) (116.3886, 48.1614) knots 0 0 0 1 2 2 2
  spline S173 degree 2 poles (116.3886, 48.1614) (115.8707, 48.3778) (115.1445, 49.2699) (114.9947, 49.9289) knots 0 0 0 1 2 2 2
  spline S174 degree 2 poles (114.9947, 49.9289) (114.9506, 50.1233) (114.911, 50.4733) (114.9245, 50.611) knots 0 0 0 1 2 2 2
  line L169 (114.9245, 50.611) -> (115.6784, 50.7823)
  line L170 (115.6784, 50.7823) -> (115.686, 50.7491)
  spline S175 degree 2 poles (115.686, 50.7491) (115.6538, 50.6272) (115.6448, 50.2063) (115.6965, 49.9787) knots 0 0 0 1 2 2 2
  spline S176 degree 2 poles (115.6965, 49.9787) (115.8624, 49.2485) (117.0522, 48.5764) (118.0388, 48.7108) knots 0 0 0 1 2 2 2
  spline S177 degree 2 poles (118.0388, 48.7108) (117.7809, 48.9464) (117.4339, 49.4859) (117.3542, 49.8367) knots 0 0 0 1 2 2 2
  spline S178 degree 2 poles (117.3542, 49.8367) (117.2766, 50.1781) (117.2978, 50.7214) (117.4429, 51.0486) knots 0 0 0 1 2 2 2
  spline S179 degree 2 poles (117.4429, 51.0486) (117.6114, 51.4259) (118.2895, 51.9091) (118.7921, 52.0232) knots 0 0 0 1 2 2 2
  spline S180 degree 2 poles (119.0062, 51.2342) (118.6459, 51.1524) (118.2006, 50.8517) (118.0773, 50.6043) knots 0 0 0 1 2 2 2
  spline S181 degree 2 poles (118.0773, 50.6043) (117.9896, 50.4199) (117.9973, 50.0128) (118.0436, 49.8089) knots 0 0 0 1 2 2 2
  spline S182 degree 2 poles (118.0436, 49.8089) (118.1061, 49.5339) (118.3895, 49.0548) (118.603, 48.839) knots 0 0 0 1 2 2 2
  spline S183 degree 2 poles (118.603, 48.839) (118.6895, 48.8537) (118.8528, 48.8808) (118.9761, 48.9088) knots 0 0 0 1 2 2 2
  spline S184 degree 2 poles (118.9761, 48.9088) (119.583, 49.0467) (120.2735, 49.4529) (120.427, 49.6772) knots 0 0 0 1 2 2 2
  spline S185 degree 2 poles (120.427, 49.6772) (120.5742, 49.8852) (120.6393, 50.2789) (120.593, 50.4828) knots 0 0 0 1 2 2 2
  spline S186 degree 2 poles (120.593, 50.4828) (120.4853, 50.957) (119.6795, 51.3872) (119.0062, 51.2342) knots 0 0 0 1 2 2 2
  point P0 (0, 0)
  constraints: 4 other
emboss "LABEL" sketch "Sketch3" operation cut depth 1 direction (0, -1, 0)
body "Solid1"
